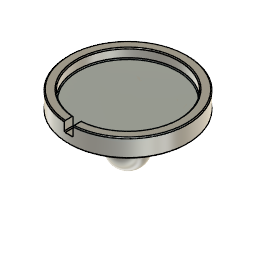
Parametric_Magsafe_Ball_Mount (Autodesk Fusion 360 design; units mm, degrees)
part number: 2025-10-10-20-44-05-017
Autodesk Fusion 360 part; units mm, degrees
sketch "Sketch1" plane through (0, 0, 0) normal (0, 0, 1) x (1, 0, 0)
  circle A0 centre (0, 0) radius 29
  dimension "d5" = 58
  constraint coincident A0.centre origin
  measures "d5" diameter of A0
extrude "Extrude1" add sketch "Sketch1" against normal blind 5 makes body 1
sketch "Sketch2" plane through (0, 0, 0) normal (0, 0, 1) x (-1, 0, 0)
  circle A0 centre (0, 0) radius 29
sketch "Sketch3" plane through (0, 0, -5) normal (0, 0, -1) x (1, 0, 0)
  circle A0 centre (0, 0) radius 29
  circle A1 centre (0, 0) radius 34
  dimension "d8" = 5
extrude "Extrude2" add sketch "Sketch3" against normal blind 10.4 bodies 1
sketch "Sketch4" plane through (0, 0, -5) normal (0, 0, -1) x (1, 0, 0)
  circle A0 centre (0, 0) radius 34
  circle A1 centre (0, 0) radius 6
  dimension "d11" = 12
  constraint coincident A0.centre A1.centre
  measures "d11" diameter of A1
extrude "Extrude3" add sketch "Sketch4" along normal blind 18 contours A1 bodies 1
sphere "SpherePrimitive1" add diameter 20 placed x (1, 0, 0) y (0, -1, 0) z (0, 0, -1) at (0, 0, -23) separate body makes body 2
sketch "Sketch10" plane through (0, 0, 0) normal (0, 0, 1) x (-1, 0, 0)
  line L0 (0, 28.5) -> (2.5, 28.5)
  line L1 (2.5, 28.5) -> (2.5, 48.5)
  line L2 (2.5, 48.5) -> (0, 48.5)
  line L3 (0, 48.5) -> (0, 28.5)
  line L4 (0, 48.5) -> (0, 28.5)
  line L5 (0, 28.5) -> (-2.5, 28.5)
  line L6 (-2.5, 28.5) -> (-2.5, 48.5)
  line L7 (-2.5, 48.5) -> (0, 48.5)
  dimension "d21" = 2.5
  dimension "d22" = 20
  constraint horizontal L0
  constraint vertical L1
  constraint horizontal L2
  constraint vertical L3
  constraint symmetric L0.start L3 L4.end
  constraint symmetric L0.end L3 L5.end
  constraint symmetric L1.end L3 L6.end
  constraint symmetric L2.end L3 L4.start
  measures "d21" distance of L0.start L0.end
  measures "d22" distance of L0.start L2.end
extrude "Extrude5" cut sketch "Sketch10" along normal blind 5.4 bodies 1
fillet "Fillet1" radius 0.5 1 edges at (0, 29, 0) on bodies 1
fillet "Fillet2" radius 0.5 1 edges at (0, 29, 5.4) on bodies 1
fillet "Fillet3" radius 0.5 1 edges at (0, 34, 5.4) on bodies 1
fillet "Fillet4" radius 0.5 1 edges at (-31.6991, 12.2949, -5) on bodies 1
fillet "Fillet5" radius 4 1 edges at (-5.594, -2.1697, -5) on bodies 1
fillet "Fillet6" radius 0.5 1 edges at (2.5, -31.1491, 0) on bodies 1
fillet "Fillet7" radius 0.5 1 edges at (-2.5, -31.1491, 0) on bodies 1
sketch "Sketch7" plane through (0, 0, 5.4) normal (0, 0, 1) x (-1, 0, 0)
  line L0 (0, -29) -> (0, -34) construction
  line L1 (3, -34) -> (-3, -34)
  line L2 (-3, -34) -> (-3, -29)
  line L3 (-3, -29) -> (3, -29)
  line L4 (3, -29) -> (3, -34)
  line L5 (3, -34) -> (-3, -29) construction
  line L6 (-3, -34) -> (3, -29) construction
  arc A0 (-2.5, 33.4066) -> (2.5, 33.4066) centre (0, 0) ccw
  line L7 (2.5, 33.4066) -> (2.5, 29.3939)
  arc A1 (-2.5, 29.3939) -> (2.5, 29.3939) centre (0, 0) ccw
  line L8 (-2.5, 29.3939) -> (-2.5, 33.4066)
  point P0 (0, -31.5)
  constraint horizontal L1
  constraint perpendicular L1 L2
  constraint parallel L1 L3
  constraint parallel L2 L4
  constraint coincident L5 P0
  constraint coincident L6 P0
  constraint midpoint L0 P0
equation "MagSafe_Diameter_mm = 57.5 mm" comment "Model adds .5 mm automaticall"
equation "Magsafe_Thickness_mm = 5.4 mm" comment "Model adds .5 mm automatically"
equation "Mount_Ball_Diameter_mm = 20 mm" comment "Change  to your desired ball size"
equation "Neck_Length_mm = 8 mm" comment "Shorten or Lengthen Neck"
equation "d5 = MagSafe_Diameter_mm + 0.5 mm"
equation "d9 = -5 mm - Magsafe_Thickness_mm"
equation "d11 = Neck_Thickness_mm"
equation "Neck_Thickness_mm = 12 mm" comment "Make neck thinker / stronger"
equation "d13 = Neck_Length_mm + 10 mm"
equation "d15 = Mount_Ball_Diameter_mm"
equation "Cord_Thickness_mm = 5 mm" comment "Most cords come out of the side you can more slot bigger by changing this"
equation "d21 = Cord_Thickness_mm / 2"
equation "d23 = Magsafe_Thickness_mm"
